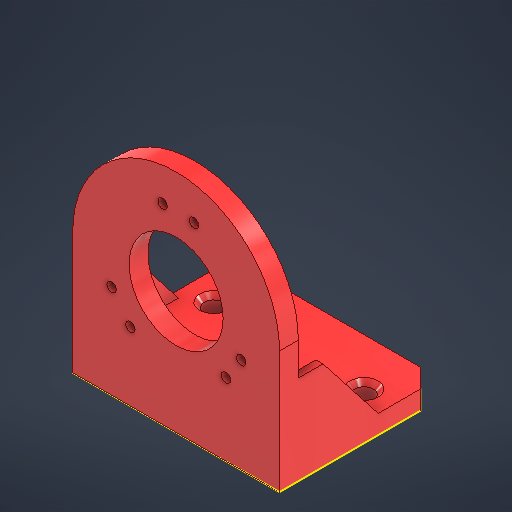
# Autodesk Inventor part: bracket for encoder
Saved by Autodesk Inventor 2027.1 (Build 311270010, 270A)
## iProperties
Created: 2026-10-20
Part Number: bracket for encoder
Material: Printed PLA Plastic
Document SubType Name: Modeling
Designer: youss
Density: 1.14 g/cm^3
Appearance: Light Red
Author: youss
Autodesk Inventor part; units mm, degrees
ref_plane "YZ Plane" through (0, 0, 0) normal (1, 0, 0) x (0, 1, 0)
sketch "Sketch1" plane through (0, 0, 0) normal (0, 0, 1) x (1, 0, 0)
  circle A0 centre (-9.7222, -11.4227) radius 1
  circle A1 centre (-2.8689, 14.7231) radius 1
  circle A2 centre (10.6066, -10.6066) radius 1
  circle A3 centre (13.8582, -5.7403) radius 1
  circle A4 centre (-13.7156, -6.0732) radius 1
  circle A5 centre (3.8033, 14.5098) radius 1
  circle A6 centre (0, 0) radius 10
  circle A7 centre (0, 0) radius 19
  circle A8 centre (0, 0) radius 9.75
  circle A9 centre (0, 0) radius 7.25
  circle A10 centre (0, 0) radius 3
  circle A11 centre (0, 0) radius 7.5
  circle A12 centre (0, 0) radius 22
  dimension "d13" = 3
  constraints: 13 centre point
  measures "d13" radial gap between concentric circles of A7 A12
extrude "Extrusion1" add sketch "Sketch1" along normal blind 4 contours A7 | A12
sketch "Sketch4" plane through (0, 0, 0) normal (0, 0, -1) x (-1, 0, 0)
  line L0 (-22, 0) -> (22, 0)
  line L1 (22, 0) -> (22, -26)
  line L2 (22, -26) -> (-22, -26)
  line L3 (-22, -26) -> (-22, 0)
  circle A0 centre (0, 0) radius 22 projected
  point P0 (0, 0)
  point P1 (0, 0)
  dimension "d7" = 26
  constraints: 8 end point, 2 midpoint, 2 parallel, 2 tangent, 1 horizontal, 1 perpendicular
  measures "d7" distance from line of point (0, 0) L2
extrude "Extrusion3" add sketch "Sketch4" against normal blind 4 contours A0 L1 L2 L3
sketch "Sketch5" plane through (0, 0, 0) normal (0, 0, -1) x (-1, 0, 0)
  line L0 (-22, -26) -> (22, -26) projected
  line L1 (22, 0) -> (22, -26) projected
  line L2 (-22, -26) -> (22, -26)
  line L3 (22, -26) -> (22, -22)
  line L4 (22, -22) -> (-22, -22)
  line L5 (-22, -22) -> (-22, -26)
  point P0 (0, 0)
  point P1 (19, 0)
  dimension "d10" = 4
  constraints: 8 end point, 2 parallel, 1 horizontal, 1 perpendicular, 2 other
  measures "d10" distance between parallel lines of L0 L4
extrude "Extrusion4" add sketch "Sketch5" along normal blind 30
sketch "Sketch6" plane through (0, 0, 0) normal (0, 0, -1) x (-1, 0, 0)
  line L0 (-22, 0) -> (-22, -22) projected
  line L1 (-22, -7) -> (-20.5, -7)
  line L2 (-20.5, -7) -> (-20.5, -22)
  line L3 (-20.5, -22) -> (-22, -22)
  line L4 (-22, -22) -> (-22, -7)
  line L5 (-22, -22) -> (22, -22) projected
  point P0 (0, 0)
  point P1 (-19, 0)
  point P2 (-21.25, -22)
  point P3 (-21.25, -7)
  dimension "d14" = 1.5
  dimension "d15" = 15
  constraints: 8 end point, 2 midpoint, 2 parallel, 1 collinear, 1 horizontal, 1 perpendicular, 2 other
  measures "d15" distance of point (-21.25, -22) point (-21.25, -7)
extrude "Extrusion5" add sketch "Sketch6" along normal blind 17
chamfer "Chamfer1" distance 15 distance2 11.75 1 edges at (21.25, -7, -17) measured on face at (21.25, -7.5, -17)
ref_plane "Work Plane2" through (0, -26, 4) normal (1, 0, 0) x (0, 0, -1)
mirror "Mirror1" about plane through (0, -26, 4) normal (1, 0, 0) of "Extrusion5", "Chamfer1"
sketch "Sketch8" plane through (-22, -22, -30) normal (0, 1, 0) x (1, 0, 0)
  circle A0 centre (38, -24) radius 2
  line L0 (0, -30) -> (44, -30) projected
  line L1 (44, -30) -> (44, -24.75) projected
  point P0 (22, -30)
  dimension "d22" = 4
  dimension "d23" = 6
  dimension "d24" = 6
  constraints: 1 centre point
  measures "d22" diameter of A0
  measures "d23" distance from line of L0 A0.centre
  measures "d24" distance from line of L1 A0.centre
extrude "Extrusion6" cut sketch "Sketch8" against normal blind 36.5
chamfer "Chamfer2" distance 4 angle 45 2 edges at (22, -24, -30) (-22, -24, -30)
mirror "Mirror2" about plane through (0, 0, 0) normal (1, 0, 0) of "Extrusion6"
ref_plane "Work Plane3" through (0, 0, -13) normal (0, 0, -1) x (-1, 0, 0)
mirror "Mirror3" about plane through (0, 0, -13) normal (0, 0, -1) of "Extrusion6", "Mirror2"
chamfer "Chamfer3" distance 1 angle 45 4 edges at (14, -22, -6) (-14, -22, -6) (-14, -22, -20) (14, -22, -20)
sketch "Sketch9" plane through (-22, -26, 4) normal (0, -1, 0) x (1, 0, 0)
  circle A0 centre (6, -24) radius 2 projected
  circle A1 centre (38, -24) radius 2 projected
  circle A2 centre (6, -10) radius 2 projected
  line L0 (4, -34) -> (0, -30) projected
  line L1 (40, -34) -> (4, -34) projected
  line L2 (44, -30) -> (40, -34) projected
  line L3 (44, 0) -> (44, -30) projected
  line L4 (0, 0) -> (44, 0) projected
  line L5 (0, -30) -> (0, 0) projected
  circle A3 centre (38, -10) radius 2 projected
  point P0 (22, -4)
body "Solid1"
